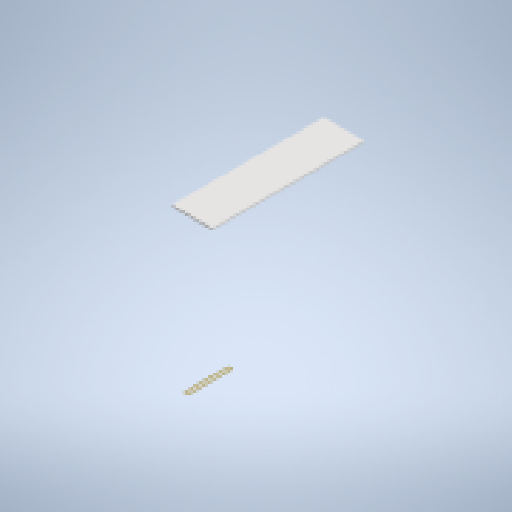
# Autodesk Inventor part: RDS-5005 Panel Plate 750x200
Saved by Autodesk Inventor 2026 (Build 300175000, 175)
## iProperties
Created: 2026-10-26
Part Number: RDS-5005 Panel Plate 750x200
Material: Типовые
Document SubType Name: Modeling
Designer: user
Density: 1 g/cm^3
Appearance: По умолчанию
Author: user
Autodesk Inventor part; units mm, degrees
ref_plane "YZ Plane" through (0, 0, 0) normal (1, 0, 0) x (0, 1, 0)
ref_plane "XZ Plane" through (0, 0, 0) normal (0, 1, 0) x (-1, 0, 0)
ref_plane "XY Plane" through (0, 0, 0) normal (0, 0, 1) x (1, 0, 0)
sketch "Эскиз1" plane through (0, 0, 0) normal (0, 1, 0) x (-1, 0, 0)
  line L0 (-100, 375) -> (100, 375)
  line L1 (100, 375) -> (100, -375)
  line L2 (100, -375) -> (-100, -375)
  line L3 (-100, -375) -> (-100, 375)
  line L4 (-100, 375) -> (100, -375) construction
  line L5 (100, 375) -> (-100, -375) construction
  point P0 (0, 0)
  dimension "d0" = 200
  dimension "d1" = 750
  constraints: 12 end point, 2 midpoint, 2 parallel, 1 horizontal, 1 perpendicular
  measures "d0" distance of L1.end L2.end
  measures "d1" distance of L0.end L1.end
extrude "Выдавливание1" add sketch "Эскиз1" along normal blind 10
